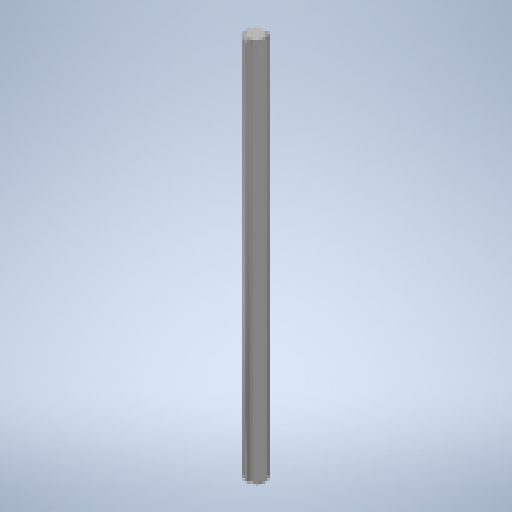
# Autodesk Inventor part: 77MM-4MM ROD
Saved by Autodesk Inventor 2026.3 (Build 303398000, 398)
## iProperties
Created: 2026-10-21
Part Number: 77MM-4MM ROD
Material: Stainless Steel
Document SubType Name: Modeling
Designer: Salim
Density: 8 g/cm^3
Appearance: Semi-Polished
Author: Salim
Autodesk Inventor part; units mm, degrees
ref_plane "YZ Plane" through (0, 0, 0) normal (1, 0, 0) x (0, 1, 0)
ref_plane "XZ Plane" through (0, 0, 0) normal (0, 1, 0) x (-1, 0, 0)
ref_plane "XY Plane" through (0, 0, 0) normal (0, 0, 1) x (1, 0, 0)
sketch "Sketch1" plane through (0, 0, 0) normal (0, 1, 0) x (-1, 0, 0)
  circle A0 centre (0, 0) radius 2
  dimension "d0" = 4
  constraints: 1 centre point, 1 coincident
  measures "d0" diameter of A0
extrude "Extrusion1" add sketch "Sketch1" along normal blind 77
chamfer "Chamfer1" distance 0.5 angle 45 2 edges at (2, 77, 0) (2, 0, 0)
body "Solid1"
